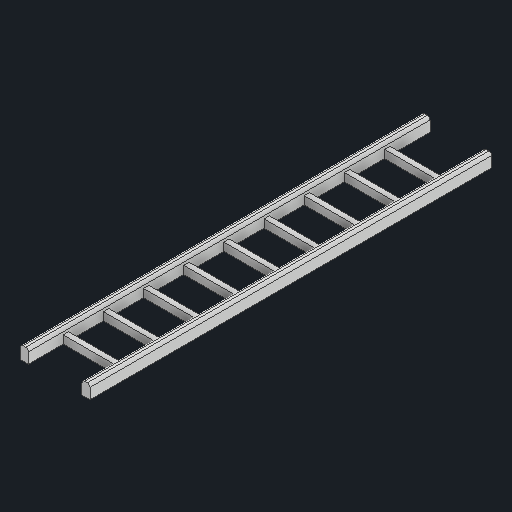
# Autodesk Inventor part: 7_5_3_echelle
Saved by Autodesk Inventor 2026 (Build 300175000, 175)
## iProperties
Created: 2025-06-22
Part Number: 7_5_3_echelle
Material: Generic
Document SubType Name: Modeling
Designer: remg9
Density: 1 g/cm^3
Appearance: Default
Author: remg9
Autodesk Inventor part; units mm, degrees
ref_plane "YZ Plane" through (0, 0, 0) normal (1, 0, 0) x (0, 1, 0)
ref_plane "XZ Plane" through (0, 0, 0) normal (0, 1, 0) x (-1, 0, 0)
ref_plane "XY Plane" through (0, 0, 0) normal (0, 0, 1) x (1, 0, 0)
sketch "Sketch1" plane through (0, 0, 0) normal (0, 0, 1) x (1, 0, 0)
  line L0 (0, 0) -> (3, 0)
  line L1 (3, 0) -> (3, 4)
  line L2 (2, 5) -> (1, 5)
  line L3 (0, 4) -> (0, 0)
  line L4 (23, 0) -> (26, 0)
  line L5 (26, 0) -> (26, 4)
  line L6 (25, 5) -> (24, 5)
  line L7 (23, 4) -> (23, 0)
  arc A0 (26, 4) -> (25, 5) centre (25, 4) ccw
  arc A1 (24, 5) -> (23, 4) centre (24, 4) ccw
  arc A2 (1, 5) -> (0, 4) centre (1, 4) ccw
  arc A3 (3, 4) -> (2, 5) centre (2, 4) ccw
  point P0 (3, 5)
  point P1 (0, 5)
  point P2 (26, 5)
  point P3 (23, 5)
  dimension "d0" = 3
  dimension "d1" = 5
  dimension "d2" = 3
  dimension "d3" = 20
  dimension "d6" = 1
  constraints: 16 end point, 10 point on line, 8 point on circle, 8 tangent, 4 centre point, 4 parallel, 3 equal radius, 2 horizontal, 2 perpendicular
  measures "d0" distance of point (3, 5) point (0, 5)
  measures "d1" distance of L0.end point (3, 5)
  measures "d2" distance of point (26, 5) point (23, 5)
  measures "d3" distance between parallel lines of L7 L1
  measures "d6" radius of A0
extrude "Extrusion1" add sketch "Sketch1" along normal blind 150
sketch "Sketch2" plane through (26, 0, 0) normal (0, -1, 0) x (1, 0, 0)
  line L0 (0, 15) -> (-26, 15)
  line L1 (-26, 15) -> (-26, 17)
  line L2 (-26, 17) -> (0, 17)
  line L3 (0, 17) -> (0, 15)
  line L4 (0, 0) -> (0, 150) projected
  line L5 (-26, 0) -> (-26, 150) projected
  line L6 (-26, 0) -> (-23, 0) projected
  line L7 (0, 30) -> (-26, 30)
  line L8 (-26, 30) -> (-26, 32)
  line L9 (-26, 32) -> (0, 32)
  line L10 (0, 32) -> (0, 30)
  line L11 (0, 45) -> (-26, 45)
  line L12 (-26, 45) -> (-26, 47)
  line L13 (-26, 47) -> (0, 47)
  line L14 (0, 47) -> (0, 45)
  line L15 (0, 60) -> (-26, 60)
  line L16 (-26, 60) -> (-26, 62)
  line L17 (-26, 62) -> (0, 62)
  line L18 (0, 62) -> (0, 60)
  line L19 (0, 75) -> (-26, 75)
  line L20 (-26, 75) -> (-26, 77)
  line L21 (-26, 77) -> (0, 77)
  line L22 (0, 77) -> (0, 75)
  line L23 (0, 90) -> (-26, 90)
  line L24 (-26, 90) -> (-26, 92)
  line L25 (-26, 92) -> (0, 92)
  line L26 (0, 92) -> (0, 90)
  line L27 (0, 105) -> (-26, 105)
  line L28 (-26, 105) -> (-26, 107)
  line L29 (-26, 107) -> (0, 107)
  line L30 (0, 107) -> (0, 105)
  line L31 (0, 120) -> (-26, 120)
  line L32 (-26, 120) -> (-26, 122)
  line L33 (-26, 122) -> (0, 122)
  line L34 (0, 122) -> (0, 120)
  line L35 (0, 135) -> (-26, 135)
  line L36 (-26, 135) -> (-26, 137)
  line L37 (-26, 137) -> (0, 137)
  line L38 (0, 137) -> (0, 135)
  point P0 (0, 137)
  point P1 (0, 135)
  point P2 (0, 122)
  point P3 (0, 120)
  point P4 (0, 107)
  point P5 (0, 105)
  point P6 (0, 92)
  point P7 (0, 90)
  point P8 (0, 77)
  point P9 (0, 75)
  point P10 (0, 62)
  point P11 (0, 60)
  point P12 (0, 47)
  point P13 (0, 45)
  point P14 (0, 32)
  point P15 (0, 30)
  dimension "d7" = 2
  dimension "d8" = 15
  dimension "d11" = 15
  constraints: 72 end point, 2 collinear, 2 parallel, 1 horizontal, 1 perpendicular, 1 vertical, 64 other
  measures "d7" distance between parallel lines of L2 L0
  measures "d8" distance between parallel lines of L6 L0
  measures "d11" distance of L0.start L7.start
extrude "Extrusion2" add sketch "Sketch2" against normal blind 3 contours L0 L1 L2 L3 | L7 L5 L9 L4 | L11 L5 L13 L4 | L15 L5 L17 L4 | L19 L5 L21 L4 | L23 L5 L25 L4 | L27 L5 L29 L4 | L31 L5 L33 L4 | L35 L5 L37 L4
body "Solid1"
